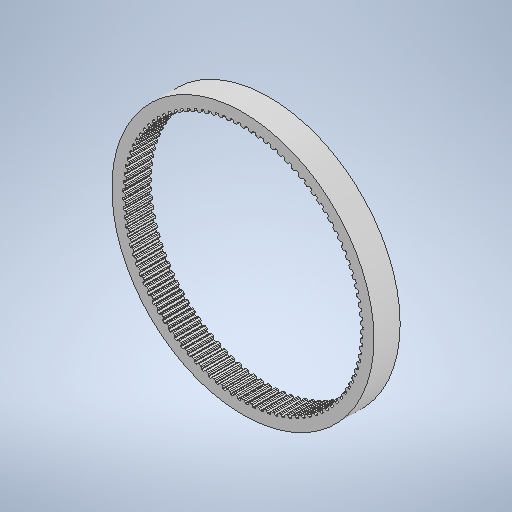
# Autodesk Inventor part: 3D_belt-MXL-100
Saved by Autodesk Inventor 2025.3 (Build 293356030, 356C)
## iProperties
Created: 2026-02-24
Part Number: 3D_belt-MXL-100
Material: 一般
Document SubType Name: Modeling
Designer: ibuki_ono
Density: 1 g/cm^3
Appearance: 既定
Author: ibuki_ono
## iProperties of the stored document 3D_belt-MXL-100_3D プリント.ipt
Created: 2026-02-24
Part Number: 3D_belt-MXL-100_3D プリント
Material: 一般
Document SubType Name: Modeling
Designer: ibuki_ono
Density: 1 g/cm^3
Appearance: 既定
Author: ibuki_ono
Autodesk Inventor part; units mm, degrees
(part 1 of 2)
ref_plane "YZ Plane" through (0, 0, 0) normal (1, 0, 0) x (0, 1, 0)
ref_plane "XZ Plane" through (0, 0, 0) normal (0, 1, 0) x (-1, 0, 0)
ref_plane "XY Plane" through (0, 0, 0) normal (0, 0, 1) x (1, 0, 0)
sketch "スケッチ1" plane through (0, 0, 0) normal (0, 0, 1) x (1, 0, 0)
  arc A0 (2.7701, 31.9665) -> (2.6427, 31.8908) centre (2.7591, 31.84) ccw
  line L0 (2.6427, 31.8908) -> (2.4611, 31.4752)
  arc A1 (2.2124, 31.3234) -> (2.4611, 31.4752) centre (2.2284, 31.5769) ccw
  line L1 (2.2124, 31.3234) -> (1.7309, 31.3537)
  arc A2 (1.5032, 31.5355) -> (1.7309, 31.3537) centre (1.7468, 31.6072) ccw
  line L2 (1.5032, 31.5355) -> (1.3751, 31.9706)
  arc A3 (1.3751, 31.9706) -> (1.2583, 32.0616) centre (1.2533, 31.9347) ccw
  arc A4 (1.2583, 32.0616) -> (0.7574, 32.0773) centre (0, 0) ccw
  arc A5 (0.7574, 32.0773) -> (0.6351, 31.9938) centre (0.7544, 31.9504) ccw
  line L3 (0.6351, 31.9938) -> (0.4799, 31.5676)
  arc A6 (0.2412, 31.4005) -> (0.4799, 31.5676) centre (0.2412, 31.6545) ccw
  line L4 (0.2412, 31.4005) -> (-0.2412, 31.4005)
  arc A7 (-0.4799, 31.5676) -> (-0.2412, 31.4005) centre (-0.2412, 31.6545) ccw
  line L5 (-0.4799, 31.5676) -> (-0.6351, 31.9938)
  arc A8 (-0.6351, 31.9938) -> (-0.7574, 32.0773) centre (-0.7544, 31.9504) ccw
  arc A9 (-0.7574, 32.0773) -> (-1.2583, 32.0616) centre (0, 0) ccw
  arc A10 (-1.2583, 32.0616) -> (-1.3751, 31.9706) centre (-1.2533, 31.9347) ccw
  line L6 (-1.3751, 31.9706) -> (-1.5032, 31.5355)
  arc A11 (-1.7309, 31.3537) -> (-1.5032, 31.5355) centre (-1.7468, 31.6072) ccw
  line L7 (-1.7309, 31.3537) -> (-2.2124, 31.3234)
  arc A12 (-2.4611, 31.4752) -> (-2.2124, 31.3234) centre (-2.2284, 31.5769) ccw
  line L8 (-2.4611, 31.4752) -> (-2.6427, 31.8908)
  arc A13 (-2.6427, 31.8908) -> (-2.7701, 31.9665) centre (-2.7591, 31.84) ccw
  arc A14 (-2.7701, 31.9665) -> (-3.2689, 31.9193) centre (0, 0) ccw
  arc A15 (-3.2689, 31.9193) -> (-3.3798, 31.8211) centre (-3.256, 31.793) ccw
  line L9 (-3.3798, 31.8211) -> (-3.4803, 31.3788)
  arc A16 (-3.6962, 31.1831) -> (-3.4803, 31.3788) centre (-3.728, 31.4351) ccw
  line L10 (-3.6962, 31.1831) -> (-4.1749, 31.1226)
  arc A17 (-4.4326, 31.2585) -> (-4.1749, 31.1226) centre (-4.2067, 31.3746) ccw
  line L11 (-4.4326, 31.2585) -> (-4.6399, 31.6619)
  arc A18 (-4.6399, 31.6619) -> (-4.7718, 31.7295) centre (-4.7529, 31.6039) ccw
  arc A19 (-4.7718, 31.7295) -> (-5.2667, 31.6511) centre (0, 0) ccw
  arc A20 (-5.2667, 31.6511) -> (-5.3712, 31.5461) centre (-5.2459, 31.5258) ccw
  line L12 (-5.3712, 31.5461) -> (-5.4438, 31.0984)
  arc A21 (-5.6469, 30.8895) -> (-5.4438, 31.0984) centre (-5.6945, 31.139) ccw
  line L13 (-5.6469, 30.8895) -> (-6.1208, 30.7991)
  arc A22 (-6.3866, 30.9185) -> (-6.1208, 30.7991) centre (-6.1684, 31.0486) ccw
  line L14 (-6.3866, 30.9185) -> (-6.6188, 31.3081)
  arc A23 (-6.6188, 31.3081) -> (-6.7547, 31.3672) centre (-6.7279, 31.2431) ccw
  arc A24 (-6.7547, 31.3672) -> (-7.2437, 31.2579) centre (0, 0) ccw
  arc A25 (-7.2437, 31.2579) -> (-7.3414, 31.1466) centre (-7.215, 31.1342) ccw
  line L15 (-7.3414, 31.1466) -> (-7.3857, 30.6952)
  arc A26 (-7.5753, 30.474) -> (-7.3857, 30.6952) centre (-7.6385, 30.72) ccw
  line L16 (-7.5753, 30.474) -> (-8.0427, 30.354)
  arc A27 (-8.3154, 30.4565) -> (-8.0427, 30.354) centre (-8.1058, 30.6) ccw
  line L17 (-8.3154, 30.4565) -> (-8.5716, 30.8307)
  arc A28 (-8.5716, 30.8307) -> (-8.7109, 30.8812) centre (-8.6764, 30.759) ccw
  arc A29 (-8.7109, 30.8812) -> (-9.1921, 30.7414) centre (0, 0) ccw
  arc A30 (-9.1921, 30.7414) -> (-9.2827, 30.6242) centre (-9.1557, 30.6197) ccw
  line L18 (-9.2827, 30.6242) -> (-9.2985, 30.1709)
  arc A31 (-9.4738, 29.9382) -> (-9.2985, 30.1709) centre (-9.5523, 30.1798) ccw
  line L19 (-9.4738, 29.9382) -> (-9.9327, 29.7891)
  arc A32 (-10.2114, 29.8743) -> (-9.9327, 29.7891) centre (-10.0112, 30.0307) ccw
  line L20 (-10.2114, 29.8743) -> (-10.4906, 30.2317)
  arc A33 (-10.4906, 30.2317) -> (-10.6328, 30.2733) centre (-10.5907, 30.1535) ccw
  arc A34 (-10.6328, 30.2733) -> (-11.1043, 30.1036) centre (0, 0) ccw
  arc A35 (-11.1043, 30.1036) -> (-11.1872, 29.9809) centre (-11.0603, 29.9844) ccw
  line L21 (-11.1872, 29.9809) -> (-11.1746, 29.5275)
  arc A36 (-11.335, 29.2842) -> (-11.1746, 29.5275) centre (-11.4285, 29.5204) ccw
  line L22 (-11.335, 29.2842) -> (-11.7836, 29.1066)
  arc A37 (-12.067, 29.1741) -> (-11.7836, 29.1066) centre (-11.8771, 29.3428) ccw
  line L23 (-12.067, 29.1741) -> (-12.3682, 29.5133)
  arc A38 (-12.3682, 29.5133) -> (-12.5127, 29.5459) centre (-12.4631, 29.429) ccw
  arc A39 (-12.5127, 29.5459) -> (-12.9726, 29.3469) centre (0, 0) ccw
  arc A40 (-12.9726, 29.3469) -> (-13.0477, 29.2193) centre (-12.9212, 29.2308) ccw
  line L24 (-13.0477, 29.2193) -> (-13.0066, 28.7676)
  arc A41 (-13.1514, 28.5147) -> (-13.0066, 28.7676) centre (-13.2595, 28.7446) ccw
  line L25 (-13.1514, 28.5147) -> (-13.588, 28.3093)
  arc A42 (-13.8751, 28.3589) -> (-13.588, 28.3093) centre (-13.6961, 28.5391) ccw
  line L26 (-13.8751, 28.3589) -> (-14.1969, 28.6785)
  arc A43 (-14.1969, 28.6785) -> (-14.3432, 28.702) centre (-14.2864, 28.5884) ccw
  arc A44 (-14.3432, 28.702) -> (-14.7897, 28.4745) centre (0, 0) ccw
  arc A45 (-14.7897, 28.4745) -> (-14.8566, 28.3423) centre (-14.7311, 28.3618) ccw
  line L27 (-14.8566, 28.3423) -> (-14.7872, 27.8941)
  arc A46 (-14.9159, 27.6327) -> (-14.7872, 27.8941) centre (-15.0383, 27.8553) ccw
  line L28 (-14.9159, 27.6327) -> (-15.3387, 27.4002)
  arc A47 (-15.6284, 27.4317) -> (-15.3387, 27.4002) centre (-15.4611, 27.6228) ccw
  line L29 (-15.6284, 27.4317) -> (-15.9696, 27.7305)
  arc A48 (-15.9696, 27.7305) -> (-16.1171, 27.7447) centre (-16.0533, 27.6349) ccw
  arc A49 (-16.1171, 27.7447) -> (-16.5484, 27.4896) centre (0, 0) ccw
  arc A50 (-16.5484, 27.4896) -> (-16.6069, 27.3536) centre (-16.4829, 27.3808) ccw
  line L30 (-16.6069, 27.3536) -> (-16.5096, 26.9106)
  arc A51 (-16.6215, 26.6416) -> (-16.5096, 26.9106) centre (-16.7576, 26.856) ccw
  line L31 (-16.6215, 26.6416) -> (-17.0289, 26.383)
  arc A52 (-17.32, 26.3963) -> (-17.0289, 26.383) centre (-17.165, 26.5975) ccw
  line L32 (-17.32, 26.3963) -> (-17.6793, 26.673)
  arc A53 (-17.6793, 26.673) -> (-17.8274, 26.678) centre (-17.7568, 26.5724) ccw
  arc A54 (-17.8274, 26.678) -> (-18.2418, 26.3963) centre (0, 0) ccw
  arc A55 (-18.2418, 26.3963) -> (-18.2917, 26.2568) centre (-18.1696, 26.2918) ccw
  line L33 (-18.2917, 26.2568) -> (-18.1667, 25.8208)
  arc A56 (-18.2616, 25.5453) -> (-18.1667, 25.8208) centre (-18.4109, 25.7508) ccw
  line L34 (-18.2616, 25.5453) -> (-18.6519, 25.2617)
  arc A57 (-18.9432, 25.2566) -> (-18.6519, 25.2617) centre (-18.8012, 25.4672) ccw
  line L35 (-18.9432, 25.2566) -> (-19.3193, 25.5103)
  arc A58 (-19.3193, 25.5103) -> (-19.4673, 25.5059) centre (-19.3903, 25.405) ccw
  arc A59 (-19.4673, 25.5059) -> (-19.8633, 25.1988) centre (0, 0) ccw
  arc A60 (-19.8633, 25.1988) -> (-19.9043, 25.0565) centre (-19.7847, 25.0991) ccw
  line L36 (-19.9043, 25.0565) -> (-19.7522, 24.6292)
  arc A61 (-19.8295, 24.3483) -> (-19.7522, 24.6292) centre (-19.9914, 24.544) ccw
  line L37 (-19.8295, 24.3483) -> (-20.2013, 24.0407)
  arc A62 (-20.4917, 24.0173) -> (-20.2013, 24.0407) centre (-20.3632, 24.2364) ccw
  line L38 (-20.4917, 24.0173) -> (-20.8829, 24.2469)
  arc A63 (-20.8829, 24.2469) -> (-21.0305, 24.2332) centre (-20.9472, 24.1373) ccw
  arc A64 (-21.0305, 24.2332) -> (-21.4063, 23.9018) centre (0, 0) ccw
  arc A65 (-21.4063, 23.9018) -> (-21.4383, 23.7572) centre (-21.3216, 23.8072) ccw
  line L39 (-21.4383, 23.7572) -> (-21.2597, 23.3403)
  arc A66 (-21.3192, 23.0551) -> (-21.2597, 23.3403) centre (-21.4931, 23.2403) ccw
  line L40 (-21.3192, 23.0551) -> (-21.671, 22.7248)
  arc A67 (-21.9594, 22.6833) -> (-21.671, 22.7248) centre (-21.8448, 22.91) ccw
  line L41 (-21.9594, 22.6833) -> (-22.3642, 22.8878)
  arc A68 (-22.3642, 22.8878) -> (-22.5106, 22.8649) centre (-22.4215, 22.7744) ccw
  arc A69 (-22.5106, 22.8649) -> (-22.8649, 22.5106) centre (0, 0) ccw
  arc A70 (-22.8649, 22.5106) -> (-22.8878, 22.3642) centre (-22.7744, 22.4215) ccw
  line L42 (-22.8878, 22.3642) -> (-22.6833, 21.9594)
  arc A71 (-22.7248, 21.671) -> (-22.6833, 21.9594) centre (-22.91, 21.8448) ccw
  line L43 (-22.7248, 21.671) -> (-23.0551, 21.3192)
  arc A72 (-23.3403, 21.2597) -> (-23.0551, 21.3192) centre (-23.2403, 21.4931) ccw
  line L44 (-23.3403, 21.2597) -> (-23.7572, 21.4383)
  arc A73 (-23.7572, 21.4383) -> (-23.9018, 21.4063) centre (-23.8072, 21.3216) ccw
  arc A74 (-23.9018, 21.4063) -> (-24.2332, 21.0305) centre (0, 0) ccw
  arc A75 (-24.2332, 21.0305) -> (-24.2469, 20.8829) centre (-24.1373, 20.9472) ccw
  line L45 (-24.2469, 20.8829) -> (-24.0173, 20.4917)
  arc A76 (-24.0407, 20.2013) -> (-24.0173, 20.4917) centre (-24.2364, 20.3632) ccw
  line L46 (-24.0407, 20.2013) -> (-24.3483, 19.8295)
  arc A77 (-24.6292, 19.7522) -> (-24.3483, 19.8295) centre (-24.544, 19.9914) ccw
  line L47 (-24.6292, 19.7522) -> (-25.0565, 19.9043)
  arc A78 (-25.0565, 19.9043) -> (-25.1988, 19.8633) centre (-25.0991, 19.7847) ccw
  arc A79 (-25.1988, 19.8633) -> (-25.5059, 19.4673) centre (0, 0) ccw
  arc A80 (-25.5059, 19.4673) -> (-25.5103, 19.3193) centre (-25.405, 19.3903) ccw
  line L48 (-25.5103, 19.3193) -> (-25.2566, 18.9432)
  arc A81 (-25.2617, 18.6519) -> (-25.2566, 18.9432) centre (-25.4672, 18.8012) ccw
  line L49 (-25.2617, 18.6519) -> (-25.5453, 18.2616)
  arc A82 (-25.8208, 18.1667) -> (-25.5453, 18.2616) centre (-25.7508, 18.4109) ccw
  line L50 (-25.8208, 18.1667) -> (-26.2568, 18.2917)
  arc A83 (-26.2568, 18.2917) -> (-26.3963, 18.2418) centre (-26.2918, 18.1696) ccw
  arc A84 (-26.3963, 18.2418) -> (-26.678, 17.8274) centre (0, 0) ccw
  arc A85 (-26.678, 17.8274) -> (-26.673, 17.6793) centre (-26.5724, 17.7568) ccw
  line L51 (-26.673, 17.6793) -> (-26.3963, 17.32)
  arc A86 (-26.383, 17.0289) -> (-26.3963, 17.32) centre (-26.5975, 17.165) ccw
  line L52 (-26.383, 17.0289) -> (-26.6416, 16.6215)
  arc A87 (-26.9106, 16.5096) -> (-26.6416, 16.6215) centre (-26.856, 16.7576) ccw
  line L53 (-26.9106, 16.5096) -> (-27.3536, 16.6069)
  arc A88 (-27.3536, 16.6069) -> (-27.4896, 16.5484) centre (-27.3808, 16.4829) ccw
  arc A89 (-27.4896, 16.5484) -> (-27.7447, 16.1171) centre (0, 0) ccw
  arc A90 (-27.7447, 16.1171) -> (-27.7305, 15.9696) centre (-27.6349, 16.0533) ccw
  line L54 (-27.7305, 15.9696) -> (-27.4317, 15.6284)
  arc A91 (-27.4002, 15.3387) -> (-27.4317, 15.6284) centre (-27.6228, 15.4611) ccw
  line L55 (-27.4002, 15.3387) -> (-27.6327, 14.9159)
  arc A92 (-27.8941, 14.7872) -> (-27.6327, 14.9159) centre (-27.8553, 15.0383) ccw
  line L56 (-27.8941, 14.7872) -> (-28.3423, 14.8566)
  arc A93 (-28.3423, 14.8566) -> (-28.4745, 14.7897) centre (-28.3618, 14.7311) ccw
  arc A94 (-28.4745, 14.7897) -> (-28.702, 14.3432) centre (0, 0) ccw
  arc A95 (-28.702, 14.3432) -> (-28.6785, 14.1969) centre (-28.5884, 14.2864) ccw
  line L57 (-28.6785, 14.1969) -> (-28.3589, 13.8751)
  arc A96 (-28.3093, 13.588) -> (-28.3589, 13.8751) centre (-28.5391, 13.6961) ccw
  line L58 (-28.3093, 13.588) -> (-28.5147, 13.1514)
  arc A97 (-28.7676, 13.0066) -> (-28.5147, 13.1514) centre (-28.7446, 13.2595) ccw
  line L59 (-28.7676, 13.0066) -> (-29.2193, 13.0477)
  arc A98 (-29.2193, 13.0477) -> (-29.3469, 12.9726) centre (-29.2308, 12.9212) ccw
  arc A99 (-29.3469, 12.9726) -> (-29.5459, 12.5127) centre (0, 0) ccw
  arc A100 (-29.5459, 12.5127) -> (-29.5133, 12.3682) centre (-29.429, 12.4631) ccw
  line L60 (-29.5133, 12.3682) -> (-29.1741, 12.067)
  arc A101 (-29.1066, 11.7836) -> (-29.1741, 12.067) centre (-29.3428, 11.8771) ccw
  line L61 (-29.1066, 11.7836) -> (-29.2842, 11.335)
  arc A102 (-29.5275, 11.1746) -> (-29.2842, 11.335) centre (-29.5204, 11.4285) ccw
  line L62 (-29.5275, 11.1746) -> (-29.9809, 11.1872)
  arc A103 (-29.9809, 11.1872) -> (-30.1036, 11.1043) centre (-29.9844, 11.0603) ccw
  arc A104 (-30.1036, 11.1043) -> (-30.2733, 10.6328) centre (0, 0) ccw
  arc A105 (-30.2733, 10.6328) -> (-30.2317, 10.4906) centre (-30.1535, 10.5907) ccw
  line L63 (-30.2317, 10.4906) -> (-29.8743, 10.2114)
  arc A106 (-29.7891, 9.9327) -> (-29.8743, 10.2114) centre (-30.0307, 10.0112) ccw
  line L64 (-29.7891, 9.9327) -> (-29.9382, 9.4738)
  arc A107 (-30.1709, 9.2985) -> (-29.9382, 9.4738) centre (-30.1798, 9.5523) ccw
  line L65 (-30.1709, 9.2985) -> (-30.6242, 9.2827)
  arc A108 (-30.6242, 9.2827) -> (-30.7414, 9.1921) centre (-30.6197, 9.1557) ccw
  arc A109 (-30.7414, 9.1921) -> (-30.8812, 8.7109) centre (0, 0) ccw
  arc A110 (-30.8812, 8.7109) -> (-30.8307, 8.5716) centre (-30.759, 8.6764) ccw
  line L66 (-30.8307, 8.5716) -> (-30.4565, 8.3154)
  arc A111 (-30.354, 8.0427) -> (-30.4565, 8.3154) centre (-30.6, 8.1058) ccw
  line L67 (-30.354, 8.0427) -> (-30.474, 7.5753)
  arc A112 (-30.6952, 7.3857) -> (-30.474, 7.5753) centre (-30.72, 7.6385) ccw
  line L68 (-30.6952, 7.3857) -> (-31.1466, 7.3414)
  arc A113 (-31.1466, 7.3414) -> (-31.2579, 7.2437) centre (-31.1342, 7.215) ccw
  arc A114 (-31.2579, 7.2437) -> (-31.3672, 6.7547) centre (0, 0) ccw
  arc A115 (-31.3672, 6.7547) -> (-31.3081, 6.6188) centre (-31.2431, 6.7279) ccw
  line L69 (-31.3081, 6.6188) -> (-30.9185, 6.3866)
  arc A116 (-30.7991, 6.1208) -> (-30.9185, 6.3866) centre (-31.0486, 6.1684) ccw
  line L70 (-30.7991, 6.1208) -> (-30.8895, 5.6469)
  arc A117 (-31.0984, 5.4438) -> (-30.8895, 5.6469) centre (-31.139, 5.6945) ccw
  line L71 (-31.0984, 5.4438) -> (-31.5461, 5.3712)
  arc A118 (-31.5461, 5.3712) -> (-31.6511, 5.2667) centre (-31.5258, 5.2459) ccw
  arc A119 (-31.6511, 5.2667) -> (-31.7295, 4.7718) centre (0, 0) ccw
  arc A120 (-31.7295, 4.7718) -> (-31.6619, 4.6399) centre (-31.6039, 4.7529) ccw
  line L72 (-31.6619, 4.6399) -> (-31.2585, 4.4326)
  arc A121 (-31.1226, 4.1749) -> (-31.2585, 4.4326) centre (-31.3746, 4.2067) ccw
  line L73 (-31.1226, 4.1749) -> (-31.1831, 3.6962)
  arc A122 (-31.3788, 3.4803) -> (-31.1831, 3.6962) centre (-31.4351, 3.728) ccw
  line L74 (-31.3788, 3.4803) -> (-31.8211, 3.3798)
  arc A123 (-31.8211, 3.3798) -> (-31.9193, 3.2689) centre (-31.793, 3.256) ccw
  arc A124 (-31.9193, 3.2689) -> (-31.9665, 2.7701) centre (0, 0) ccw
  arc A125 (-31.9665, 2.7701) -> (-31.8908, 2.6427) centre (-31.84, 2.7591) ccw
  line L75 (-31.8908, 2.6427) -> (-31.4752, 2.4611)
  arc A126 (-31.3234, 2.2124) -> (-31.4752, 2.4611) centre (-31.5769, 2.2284) ccw
  line L76 (-31.3234, 2.2124) -> (-31.3537, 1.7309)
  arc A127 (-31.5355, 1.5032) -> (-31.3537, 1.7309) centre (-31.6072, 1.7468) ccw
  line L77 (-31.5355, 1.5032) -> (-31.9706, 1.3751)
  arc A128 (-31.9706, 1.3751) -> (-32.0616, 1.2583) centre (-31.9347, 1.2533) ccw
  arc A129 (-32.0616, 1.2583) -> (-32.0773, 0.7574) centre (0, 0) ccw
  arc A130 (-32.0773, 0.7574) -> (-31.9938, 0.6351) centre (-31.9504, 0.7544) ccw
  line L78 (-31.9938, 0.6351) -> (-31.5676, 0.4799)
  arc A131 (-31.4005, 0.2412) -> (-31.5676, 0.4799) centre (-31.6545, 0.2412) ccw
  line L79 (-31.4005, 0.2412) -> (-31.4005, -0.2412)
  arc A132 (-31.5676, -0.4799) -> (-31.4005, -0.2412) centre (-31.6545, -0.2412) ccw
  line L80 (-31.5676, -0.4799) -> (-31.9938, -0.6351)
  arc A133 (-31.9938, -0.6351) -> (-32.0773, -0.7574) centre (-31.9504, -0.7544) ccw
  arc A134 (-32.0773, -0.7574) -> (-32.0616, -1.2583) centre (0, 0) ccw
  arc A135 (-32.0616, -1.2583) -> (-31.9706, -1.3751) centre (-31.9347, -1.2533) ccw
  line L81 (-31.9706, -1.3751) -> (-31.5355, -1.5032)
  arc A136 (-31.3537, -1.7309) -> (-31.5355, -1.5032) centre (-31.6072, -1.7468) ccw
  line L82 (-31.3537, -1.7309) -> (-31.3234, -2.2124)
  arc A137 (-31.4752, -2.4611) -> (-31.3234, -2.2124) centre (-31.5769, -2.2284) ccw
  line L83 (-31.4752, -2.4611) -> (-31.8908, -2.6427)
  arc A138 (-31.8908, -2.6427) -> (-31.9665, -2.7701) centre (-31.84, -2.7591) ccw
  arc A139 (-31.9665, -2.7701) -> (-31.9193, -3.2689) centre (0, 0) ccw
  arc A140 (-31.9193, -3.2689) -> (-31.8211, -3.3798) centre (-31.793, -3.256) ccw
  line L84 (-31.8211, -3.3798) -> (-31.3788, -3.4803)
  arc A141 (-31.1831, -3.6962) -> (-31.3788, -3.4803) centre (-31.4351, -3.728) ccw
  line L85 (-31.1831, -3.6962) -> (-31.1226, -4.1749)
  arc A142 (-31.2585, -4.4326) -> (-31.1226, -4.1749) centre (-31.3746, -4.2067) ccw
  line L86 (-31.2585, -4.4326) -> (-31.6619, -4.6399)
  arc A143 (-31.6619, -4.6399) -> (-31.7295, -4.7718) centre (-31.6039, -4.7529) ccw
  arc A144 (-31.7295, -4.7718) -> (-31.6511, -5.2667) centre (0, 0) ccw
  arc A145 (-31.6511, -5.2667) -> (-31.5461, -5.3712) centre (-31.5258, -5.2459) ccw
  line L87 (-31.5461, -5.3712) -> (-31.0984, -5.4438)
  arc A146 (-30.8895, -5.6469) -> (-31.0984, -5.4438) centre (-31.139, -5.6945) ccw
  line L88 (-30.8895, -5.6469) -> (-30.7991, -6.1208)
  arc A147 (-30.9185, -6.3866) -> (-30.7991, -6.1208) centre (-31.0486, -6.1684) ccw
  line L89 (-30.9185, -6.3866) -> (-31.3081, -6.6188)
  arc A148 (-31.3081, -6.6188) -> (-31.3672, -6.7547) centre (-31.2431, -6.7279) ccw
  arc A149 (-31.3672, -6.7547) -> (-31.2579, -7.2437) centre (0, 0) ccw
  arc A150 (-31.2579, -7.2437) -> (-31.1466, -7.3414) centre (-31.1342, -7.215) ccw
  line L90 (-31.1466, -7.3414) -> (-30.6952, -7.3857)
  arc A151 (-30.474, -7.5753) -> (-30.6952, -7.3857) centre (-30.72, -7.6385) ccw
  line L91 (-30.474, -7.5753) -> (-30.354, -8.0427)
  arc A152 (-30.4565, -8.3154) -> (-30.354, -8.0427) centre (-30.6, -8.1058) ccw
  line L92 (-30.4565, -8.3154) -> (-30.8307, -8.5716)
  arc A153 (-30.8307, -8.5716) -> (-30.8812, -8.7109) centre (-30.759, -8.6764) ccw
  arc A154 (-30.8812, -8.7109) -> (-30.7414, -9.1921) centre (0, 0) ccw
  arc A155 (-30.7414, -9.1921) -> (-30.6242, -9.2827) centre (-30.6197, -9.1557) ccw
  line L93 (-30.6242, -9.2827) -> (-30.1709, -9.2985)
  arc A156 (-29.9382, -9.4738) -> (-30.1709, -9.2985) centre (-30.1798, -9.5523) ccw
  line L94 (-29.9382, -9.4738) -> (-29.7891, -9.9327)
  arc A157 (-29.8743, -10.2114) -> (-29.7891, -9.9327) centre (-30.0307, -10.0112) ccw
  line L95 (-29.8743, -10.2114) -> (-30.2317, -10.4906)
  arc A158 (-30.2317, -10.4906) -> (-30.2733, -10.6328) centre (-30.1535, -10.5907) ccw
  arc A159 (-30.2733, -10.6328) -> (-30.1036, -11.1043) centre (0, 0) ccw
  arc A160 (-30.1036, -11.1043) -> (-29.9809, -11.1872) centre (-29.9844, -11.0603) ccw
  line L96 (-29.9809, -11.1872) -> (-29.5275, -11.1746)
  arc A161 (-29.2842, -11.335) -> (-29.5275, -11.1746) centre (-29.5204, -11.4285) ccw
  line L97 (-29.2842, -11.335) -> (-29.1066, -11.7836)
  arc A162 (-29.1741, -12.067) -> (-29.1066, -11.7836) centre (-29.3428, -11.8771) ccw
  line L98 (-29.1741, -12.067) -> (-29.5133, -12.3682)
  arc A163 (-29.5133, -12.3682) -> (-29.5459, -12.5127) centre (-29.429, -12.4631) ccw
  arc A164 (-29.5459, -12.5127) -> (-29.3469, -12.9726) centre (0, 0) ccw
  arc A165 (-29.3469, -12.9726) -> (-29.2193, -13.0477) centre (-29.2308, -12.9212) ccw
  line L99 (-29.2193, -13.0477) -> (-28.7676, -13.0066)
  arc A166 (-28.5147, -13.1514) -> (-28.7676, -13.0066) centre (-28.7446, -13.2595) ccw
  line L100 (-28.5147, -13.1514) -> (-28.3093, -13.588)
  arc A167 (-28.3589, -13.8751) -> (-28.3093, -13.588) centre (-28.5391, -13.6961) ccw
  line L101 (-28.3589, -13.8751) -> (-28.6785, -14.1969)
  arc A168 (-28.6785, -14.1969) -> (-28.702, -14.3432) centre (-28.5884, -14.2864) ccw
  arc A169 (-28.702, -14.3432) -> (-28.4745, -14.7897) centre (0, 0) ccw
  arc A170 (-28.4745, -14.7897) -> (-28.3423, -14.8566) centre (-28.3618, -14.7311) ccw
  line L102 (-28.3423, -14.8566) -> (-27.8941, -14.7872)
  arc A171 (-27.6327, -14.9159) -> (-27.8941, -14.7872) centre (-27.8553, -15.0383) ccw
  line L103 (-27.6327, -14.9159) -> (-27.4002, -15.3387)
  arc A172 (-27.4317, -15.6284) -> (-27.4002, -15.3387) centre (-27.6228, -15.4611) ccw
  line L104 (-27.4317, -15.6284) -> (-27.7305, -15.9696)
  arc A173 (-27.7305, -15.9696) -> (-27.7447, -16.1171) centre (-27.6349, -16.0533) ccw
  arc A174 (-27.7447, -16.1171) -> (-27.4896, -16.5484) centre (0, 0) ccw
  arc A175 (-27.4896, -16.5484) -> (-27.3536, -16.6069) centre (-27.3808, -16.4829) ccw
  line L105 (-27.3536, -16.6069) -> (-26.9106, -16.5096)
  arc A176 (-26.6416, -16.6215) -> (-26.9106, -16.5096) centre (-26.856, -16.7576) ccw
  line L106 (-26.6416, -16.6215) -> (-26.383, -17.0289)
  arc A177 (-26.3963, -17.32) -> (-26.383, -17.0289) centre (-26.5975, -17.165) ccw
  line L107 (-26.3963, -17.32) -> (-26.673, -17.6793)
  arc A178 (-26.673, -17.6793) -> (-26.678, -17.8274) centre (-26.5724, -17.7568) ccw
  arc A179 (-26.678, -17.8274) -> (-26.3963, -18.2418) centre (0, 0) ccw
  arc A180 (-26.3963, -18.2418) -> (-26.2568, -18.2917) centre (-26.2918, -18.1696) ccw
  line L108 (-26.2568, -18.2917) -> (-25.8208, -18.1667)
  arc A181 (-25.5453, -18.2616) -> (-25.8208, -18.1667) centre (-25.7508, -18.4109) ccw
  line L109 (-25.5453, -18.2616) -> (-25.2617, -18.6519)
  arc A182 (-25.2566, -18.9432) -> (-25.2617, -18.6519) centre (-25.4672, -18.8012) ccw
  line L110 (-25.2566, -18.9432) -> (-25.5103, -19.3193)
  arc A183 (-25.5103, -19.3193) -> (-25.5059, -19.4673) centre (-25.405, -19.3903) ccw
  arc A184 (-25.5059, -19.4673) -> (-25.1988, -19.8633) centre (0, 0) ccw
  arc A185 (-25.1988, -19.8633) -> (-25.0565, -19.9043) centre (-25.0991, -19.7847) ccw
  line L111 (-25.0565, -19.9043) -> (-24.6292, -19.7522)
  arc A186 (-24.3483, -19.8295) -> (-24.6292, -19.7522) centre (-24.544, -19.9914) ccw
  line L112 (-24.3483, -19.8295) -> (-24.0407, -20.2013)
  arc A187 (-24.0173, -20.4917) -> (-24.0407, -20.2013) centre (-24.2364, -20.3632) ccw
  line L113 (-24.0173, -20.4917) -> (-24.2469, -20.8829)
  arc A188 (-24.2469, -20.8829) -> (-24.2332, -21.0305) centre (-24.1373, -20.9472) ccw
  arc A189 (-24.2332, -21.0305) -> (-23.9018, -21.4063) centre (0, 0) ccw
  arc A190 (-23.9018, -21.4063) -> (-23.7572, -21.4383) centre (-23.8072, -21.3216) ccw
  line L114 (-23.7572, -21.4383) -> (-23.3403, -21.2597)
  arc A191 (-23.0551, -21.3192) -> (-23.3403, -21.2597) centre (-23.2403, -21.4931) ccw
  line L115 (-23.0551, -21.3192) -> (-22.7248, -21.671)
  arc A192 (-22.6833, -21.9594) -> (-22.7248, -21.671) centre (-22.91, -21.8448) ccw
  line L116 (-22.6833, -21.9594) -> (-22.8878, -22.3642)
  arc A193 (-22.8878, -22.3642) -> (-22.8649, -22.5106) centre (-22.7744, -22.4215) ccw
  arc A194 (-22.8649, -22.5106) -> (-22.5106, -22.8649) centre (0, 0) ccw
  arc A195 (-22.5106, -22.8649) -> (-22.3642, -22.8878) centre (-22.4215, -22.7744) ccw
  line L117 (-22.3642, -22.8878) -> (-21.9594, -22.6833)
  arc A196 (-21.671, -22.7248) -> (-21.9594, -22.6833) centre (-21.8448, -22.91) ccw
  line L118 (-21.671, -22.7248) -> (-21.3192, -23.0551)
  arc A197 (-21.2597, -23.3403) -> (-21.3192, -23.0551) centre (-21.4931, -23.2403) ccw
  line L119 (-21.2597, -23.3403) -> (-21.4383, -23.7572)
  arc A198 (-21.4383, -23.7572) -> (-21.4063, -23.9018) centre (-21.3216, -23.8072) ccw
  arc A199 (-21.4063, -23.9018) -> (-21.0305, -24.2332) centre (0, 0) ccw
  arc A200 (-21.0305, -24.2332) -> (-20.8829, -24.2469) centre (-20.9472, -24.1373) ccw
  line L120 (-20.8829, -24.2469) -> (-20.4917, -24.0173)
  arc A201 (-20.2013, -24.0407) -> (-20.4917, -24.0173) centre (-20.3632, -24.2364) ccw
  line L121 (-20.2013, -24.0407) -> (-19.8295, -24.3483)
  arc A202 (-19.7522, -24.6292) -> (-19.8295, -24.3483) centre (-19.9914, -24.544) ccw
  line L122 (-19.7522, -24.6292) -> (-19.9043, -25.0565)
  arc A203 (-19.9043, -25.0565) -> (-19.8633, -25.1988) centre (-19.7847, -25.0991) ccw
  arc A204 (-19.8633, -25.1988) -> (-19.4673, -25.5059) centre (0, 0) ccw
  arc A205 (-19.4673, -25.5059) -> (-19.3193, -25.5103) centre (-19.3903, -25.405) ccw
  line L123 (-19.3193, -25.5103) -> (-18.9432, -25.2566)
  arc A206 (-18.6519, -25.2617) -> (-18.9432, -25.2566) centre (-18.8012, -25.4672) ccw
  line L124 (-18.6519, -25.2617) -> (-18.2616, -25.5453)
  arc A207 (-18.1667, -25.8208) -> (-18.2616, -25.5453) centre (-18.4109, -25.7508) ccw
  line L125 (-18.1667, -25.8208) -> (-18.2917, -26.2568)
  arc A208 (-18.2917, -26.2568) -> (-18.2418, -26.3963) centre (-18.1696, -26.2918) ccw
  arc A209 (-18.2418, -26.3963) -> (-17.8274, -26.678) centre (0, 0) ccw
  arc A210 (-17.8274, -26.678) -> (-17.6793, -26.673) centre (-17.7568, -26.5724) ccw
  line L126 (-17.6793, -26.673) -> (-17.32, -26.3963)
  arc A211 (-17.0289, -26.383) -> (-17.32, -26.3963) centre (-17.165, -26.5975) ccw
  line L127 (-17.0289, -26.383) -> (-16.6215, -26.6416)
  arc A212 (-16.5096, -26.9106) -> (-16.6215, -26.6416) centre (-16.7576, -26.856) ccw
  line L128 (-16.5096, -26.9106) -> (-16.6069, -27.3536)
  arc A213 (-16.6069, -27.3536) -> (-16.5484, -27.4896) centre (-16.4829, -27.3808) ccw
  arc A214 (-16.5484, -27.4896) -> (-16.1171, -27.7447) centre (0, 0) ccw
  arc A215 (-16.1171, -27.7447) -> (-15.9696, -27.7305) centre (-16.0533, -27.6349) ccw
  line L129 (-15.9696, -27.7305) -> (-15.6284, -27.4317)
  arc A216 (-15.3387, -27.4002) -> (-15.6284, -27.4317) centre (-15.4611, -27.6228) ccw
  line L130 (-15.3387, -27.4002) -> (-14.9159, -27.6327)
  arc A217 (-14.7872, -27.8941) -> (-14.9159, -27.6327) centre (-15.0383, -27.8553) ccw
  line L131 (-14.7872, -27.8941) -> (-14.8566, -28.3423)
  arc A218 (-14.8566, -28.3423) -> (-14.7897, -28.4745) centre (-14.7311, -28.3618) ccw
  arc A219 (-14.7897, -28.4745) -> (-14.3432, -28.702) centre (0, 0) ccw
  arc A220 (-14.3432, -28.702) -> (-14.1969, -28.6785) centre (-14.2864, -28.5884) ccw
  line L132 (-14.1969, -28.6785) -> (-13.8751, -28.3589)
  arc A221 (-13.588, -28.3093) -> (-13.8751, -28.3589) centre (-13.6961, -28.5391) ccw
  line L133 (-13.588, -28.3093) -> (-13.1514, -28.5147)
  arc A222 (-13.0066, -28.7676) -> (-13.1514, -28.5147) centre (-13.2595, -28.7446) ccw
  line L134 (-13.0066, -28.7676) -> (-13.0477, -29.2193)
  arc A223 (-13.0477, -29.2193) -> (-12.9726, -29.3469) centre (-12.9212, -29.2308) ccw
  arc A224 (-12.9726, -29.3469) -> (-12.5127, -29.5459) centre (0, 0) ccw
  arc A225 (-12.5127, -29.5459) -> (-12.3682, -29.5133) centre (-12.4631, -29.429) ccw
  line L135 (-12.3682, -29.5133) -> (-12.067, -29.1741)
  arc A226 (-11.7836, -29.1066) -> (-12.067, -29.1741) centre (-11.8771, -29.3428) ccw
  line L136 (-11.7836, -29.1066) -> (-11.335, -29.2842)
  arc A227 (-11.1746, -29.5275) -> (-11.335, -29.2842) centre (-11.4285, -29.5204) ccw
  line L137 (-11.1746, -29.5275) -> (-11.1872, -29.9809)
  arc A228 (-11.1872, -29.9809) -> (-11.1043, -30.1036) centre (-11.0603, -29.9844) ccw
  arc A229 (-11.1043, -30.1036) -> (-10.6328, -30.2733) centre (0, 0) ccw
  arc A230 (-10.6328, -30.2733) -> (-10.4906, -30.2317) centre (-10.5907, -30.1535) ccw
  line L138 (-10.4906, -30.2317) -> (-10.2114, -29.8743)
  arc A231 (-9.9327, -29.7891) -> (-10.2114, -29.8743) centre (-10.0112, -30.0307) ccw
  line L139 (-9.9327, -29.7891) -> (-9.4738, -29.9382)
  arc A232 (-9.2985, -30.1709) -> (-9.4738, -29.9382) centre (-9.5523, -30.1798) ccw
  line L140 (-9.2985, -30.1709) -> (-9.2827, -30.6242)
  arc A233 (-9.2827, -30.6242) -> (-9.1921, -30.7414) centre (-9.1557, -30.6197) ccw
  arc A234 (-9.1921, -30.7414) -> (-8.7109, -30.8812) centre (0, 0) ccw
  arc A235 (-8.7109, -30.8812) -> (-8.5716, -30.8307) centre (-8.6764, -30.759) ccw
  line L141 (-8.5716, -30.8307) -> (-8.3154, -30.4565)
  arc A236 (-8.0427, -30.354) -> (-8.3154, -30.4565) centre (-8.1058, -30.6) ccw
  line L142 (-8.0427, -30.354) -> (-7.5753, -30.474)
  arc A237 (-7.3857, -30.6952) -> (-7.5753, -30.474) centre (-7.6385, -30.72) ccw
  line L143 (-7.3857, -30.6952) -> (-7.3414, -31.1466)
  arc A238 (-7.3414, -31.1466) -> (-7.2437, -31.2579) centre (-7.215, -31.1342) ccw
  arc A239 (-7.2437, -31.2579) -> (-6.7547, -31.3672) centre (0, 0) ccw
  arc A240 (-6.7547, -31.3672) -> (-6.6188, -31.3081) centre (-6.7279, -31.2431) ccw
  line L144 (-6.6188, -31.3081) -> (-6.3866, -30.9185)
  arc A241 (-6.1208, -30.7991) -> (-6.3866, -30.9185) centre (-6.1684, -31.0486) ccw
  line L145 (-6.1208, -30.7991) -> (-5.6469, -30.8895)
  arc A242 (-5.4438, -31.0984) -> (-5.6469, -30.8895) centre (-5.6945, -31.139) ccw
  line L146 (-5.4438, -31.0984) -> (-5.3712, -31.5461)
  arc A243 (-5.3712, -31.5461) -> (-5.2667, -31.6511) centre (-5.2459, -31.5258) ccw
  arc A244 (-5.2667, -31.6511) -> (-4.7718, -31.7295) centre (0, 0) ccw
  arc A245 (-4.7718, -31.7295) -> (-4.6399, -31.6619) centre (-4.7529, -31.6039) ccw
  line L147 (-4.6399, -31.6619) -> (-4.4326, -31.2585)
  arc A246 (-4.1749, -31.1226) -> (-4.4326, -31.2585) centre (-4.2067, -31.3746) ccw
  line L148 (-4.1749, -31.1226) -> (-3.6962, -31.1831)
  arc A247 (-3.4803, -31.3788) -> (-3.6962, -31.1831) centre (-3.728, -31.4351) ccw
  line L149 (-3.4803, -31.3788) -> (-3.3798, -31.8211)
  arc A248 (-3.3798, -31.8211) -> (-3.2689, -31.9193) centre (-3.256, -31.793) ccw
  arc A249 (-3.2689, -31.9193) -> (-2.7701, -31.9665) centre (0, 0) ccw
  arc A250 (-2.7701, -31.9665) -> (-2.6427, -31.8908) centre (-2.7591, -31.84) ccw
  line L150 (-2.6427, -31.8908) -> (-2.4611, -31.4752)
  arc A251 (-2.2124, -31.3234) -> (-2.4611, -31.4752) centre (-2.2284, -31.5769) ccw
  line L151 (-2.2124, -31.3234) -> (-1.7309, -31.3537)
  arc A252 (-1.5032, -31.5355) -> (-1.7309, -31.3537) centre (-1.7468, -31.6072) ccw
  line L152 (-1.5032, -31.5355) -> (-1.3751, -31.9706)
  arc A253 (-1.3751, -31.9706) -> (-1.2583, -32.0616) centre (-1.2533, -31.9347) ccw
  arc A254 (-1.2583, -32.0616) -> (-0.7574, -32.0773) centre (0, 0) ccw
  arc A255 (-0.7574, -32.0773) -> (-0.6351, -31.9938) centre (-0.7544, -31.9504) ccw
  line L153 (-0.6351, -31.9938) -> (-0.4799, -31.5676)
  arc A256 (-0.2412, -31.4005) -> (-0.4799, -31.5676) centre (-0.2412, -31.6545) ccw
  line L154 (-0.2412, -31.4005) -> (0.2412, -31.4005)
  arc A257 (0.4799, -31.5676) -> (0.2412, -31.4005) centre (0.2412, -31.6545) ccw
  line L155 (0.4799, -31.5676) -> (0.6351, -31.9938)
  arc A258 (0.6351, -31.9938) -> (0.7574, -32.0773) centre (0.7544, -31.9504) ccw
  arc A259 (0.7574, -32.0773) -> (1.2583, -32.0616) centre (0, 0) ccw
  arc A260 (1.2583, -32.0616) -> (1.3751, -31.9706) centre (1.2533, -31.9347) ccw
  line L156 (1.3751, -31.9706) -> (1.5032, -31.5355)
  arc A261 (1.7309, -31.3537) -> (1.5032, -31.5355) centre (1.7468, -31.6072) ccw
  line L157 (1.7309, -31.3537) -> (2.2124, -31.3234)
  arc A262 (2.4611, -31.4752) -> (2.2124, -31.3234) centre (2.2284, -31.5769) ccw
  line L158 (2.4611, -31.4752) -> (2.6427, -31.8908)
  arc A263 (2.6427, -31.8908) -> (2.7701, -31.9665) centre (2.7591, -31.84) ccw
  arc A264 (2.7701, -31.9665) -> (3.2689, -31.9193) centre (0, 0) ccw
  arc A265 (3.2689, -31.9193) -> (3.3798, -31.8211) centre (3.256, -31.793) ccw
  line L159 (3.3798, -31.8211) -> (3.4803, -31.3788)
  arc A266 (3.6962, -31.1831) -> (3.4803, -31.3788) centre (3.728, -31.4351) ccw
  line L160 (3.6962, -31.1831) -> (4.1749, -31.1226)
  arc A267 (4.4326, -31.2585) -> (4.1749, -31.1226) centre (4.2067, -31.3746) ccw
  line L161 (4.4326, -31.2585) -> (4.6399, -31.6619)
  arc A268 (4.6399, -31.6619) -> (4.7718, -31.7295) centre (4.7529, -31.6039) ccw
  arc A269 (4.7718, -31.7295) -> (5.2667, -31.6511) centre (0, 0) ccw
  arc A270 (5.2667, -31.6511) -> (5.3712, -31.5461) centre (5.2459, -31.5258) ccw
  line L162 (5.3712, -31.5461) -> (5.4438, -31.0984)
  arc A271 (5.6469, -30.8895) -> (5.4438, -31.0984) centre (5.6945, -31.139) ccw
  line L163 (5.6469, -30.8895) -> (6.1208, -30.7991)
  arc A272 (6.3866, -30.9185) -> (6.1208, -30.7991) centre (6.1684, -31.0486) ccw
  line L164 (6.3866, -30.9185) -> (6.6188, -31.3081)
  arc A273 (6.6188, -31.3081) -> (6.7547, -31.3672) centre (6.7279, -31.2431) ccw
  arc A274 (6.7547, -31.3672) -> (7.2437, -31.2579) centre (0, 0) ccw
  arc A275 (7.2437, -31.2579) -> (7.3414, -31.1466) centre (7.215, -31.1342) ccw
  line L165 (7.3414, -31.1466) -> (7.3857, -30.6952)
  arc A276 (7.5753, -30.474) -> (7.3857, -30.6952) centre (7.6385, -30.72) ccw
  line L166 (7.5753, -30.474) -> (8.0427, -30.354)
  arc A277 (8.3154, -30.4565) -> (8.0427, -30.354) centre (8.1058, -30.6) ccw
  line L167 (8.3154, -30.4565) -> (8.5716, -30.8307)
  arc A278 (8.5716, -30.8307) -> (8.7109, -30.8812) centre (8.6764, -30.759) ccw
  arc A279 (8.7109, -30.8812) -> (9.1921, -30.7414) centre (0, 0) ccw
  arc A280 (9.1921, -30.7414) -> (9.2827, -30.6242) centre (9.1557, -30.6197) ccw
  line L168 (9.2827, -30.6242) -> (9.2985, -30.1709)
  arc A281 (9.4738, -29.9382) -> (9.2985, -30.1709) centre (9.5523, -30.1798) ccw
  line L169 (9.4738, -29.9382) -> (9.9327, -29.7891)
  arc A282 (10.2114, -29.8743) -> (9.9327, -29.7891) centre (10.0112, -30.0307) ccw
  line L170 (10.2114, -29.8743) -> (10.4906, -30.2317)
  arc A283 (10.4906, -30.2317) -> (10.6328, -30.2733) centre (10.5907, -30.1535) ccw
  arc A284 (10.6328, -30.2733) -> (11.1043, -30.1036) centre (0, 0) ccw
  arc A285 (11.1043, -30.1036) -> (11.1872, -29.9809) centre (11.0603, -29.9844) ccw
  line L171 (11.1872, -29.9809) -> (11.1746, -29.5275)
  arc A286 (11.335, -29.2842) -> (11.1746, -29.5275) centre (11.4285, -29.5204) ccw
  line L172 (11.335, -29.2842) -> (11.7836, -29.1066)
  arc A287 (12.067, -29.1741) -> (11.7836, -29.1066) centre (11.8771, -29.3428) ccw
  line L173 (12.067, -29.1741) -> (12.3682, -29.5133)
  arc A288 (12.3682, -29.5133) -> (12.5127, -29.5459) centre (12.4631, -29.429) ccw
  arc A289 (12.5127, -29.5459) -> (12.9726, -29.3469) centre (0, 0) ccw
  arc A290 (12.9726, -29.3469) -> (13.0477, -29.2193) centre (12.9212, -29.2308) ccw
  line L174 (13.0477, -29.2193) -> (13.0066, -28.7676)
  arc A291 (13.1514, -28.5147) -> (13.0066, -28.7676) centre (13.2595, -28.7446) ccw
  line L175 (13.1514, -28.5147) -> (13.588, -28.3093)
  arc A292 (13.8751, -28.3589) -> (13.588, -28.3093) centre (13.6961, -28.5391) ccw
  line L176 (13.8751, -28.3589) -> (14.1969, -28.6785)
  arc A293 (14.1969, -28.6785) -> (14.3432, -28.702) centre (14.2864, -28.5884) ccw
  arc A294 (14.3432, -28.702) -> (14.7897, -28.4745) centre (0, 0) ccw
  arc A295 (14.7897, -28.4745) -> (14.8566, -28.3423) centre (14.7311, -28.3618) ccw
  line L177 (14.8566, -28.3423) -> (14.7872, -27.8941)
  arc A296 (14.9159, -27.6327) -> (14.7872, -27.8941) centre (15.0383, -27.8553) ccw
  line L178 (14.9159, -27.6327) -> (15.3387, -27.4002)
  arc A297 (15.6284, -27.4317) -> (15.3387, -27.4002) centre (15.4611, -27.6228) ccw
  line L179 (15.6284, -27.4317) -> (15.9696, -27.7305)
  arc A298 (15.9696, -27.7305) -> (16.1171, -27.7447) centre (16.0533, -27.6349) ccw
  arc A299 (16.1171, -27.7447) -> (16.5484, -27.4896) centre (0, 0) ccw
  arc A300 (16.5484, -27.4896) -> (16.6069, -27.3536) centre (16.4829, -27.3808) ccw
  line L180 (16.6069, -27.3536) -> (16.5096, -26.9106)
  arc A301 (16.6215, -26.6416) -> (16.5096, -26.9106) centre (16.7576, -26.856) ccw
  line L181 (16.6215, -26.6416) -> (17.0289, -26.383)
  arc A302 (17.32, -26.3963) -> (17.0289, -26.383) centre (17.165, -26.5975) ccw
  line L182 (17.32, -26.3963) -> (17.6793, -26.673)
  arc A303 (17.6793, -26.673) -> (17.8274, -26.678) centre (17.7568, -26.5724) ccw
  arc A304 (17.8274, -26.678) -> (18.2418, -26.3963) centre (0, 0) ccw
  arc A305 (18.2418, -26.3963) -> (18.2917, -26.2568) centre (18.1696, -26.2918) ccw
  line L183 (18.2917, -26.2568) -> (18.1667, -25.8208)
  arc A306 (18.2616, -25.5453) -> (18.1667, -25.8208) centre (18.4109, -25.7508) ccw
  line L184 (18.2616, -25.5453) -> (18.6519, -25.2617)
  arc A307 (18.9432, -25.2566) -> (18.6519, -25.2617) centre (18.8012, -25.4672) ccw
  line L185 (18.9432, -25.2566) -> (19.3193, -25.5103)
  arc A308 (19.3193, -25.5103) -> (19.4673, -25.5059) centre (19.3903, -25.405) ccw
  arc A309 (19.4673, -25.5059) -> (19.8633, -25.1988) centre (0, 0) ccw
  arc A310 (19.8633, -25.1988) -> (19.9043, -25.0565) centre (19.7847, -25.0991) ccw
  line L186 (19.9043, -25.0565) -> (19.7522, -24.6292)
  arc A311 (19.8295, -24.3483) -> (19.7522, -24.6292) centre (19.9914, -24.544) ccw
  line L187 (19.8295, -24.3483) -> (20.2013, -24.0407)
  arc A312 (20.4917, -24.0173) -> (20.2013, -24.0407) centre (20.3632, -24.2364) ccw
  line L188 (20.4917, -24.0173) -> (20.8829, -24.2469)
  arc A313 (20.8829, -24.2469) -> (21.0305, -24.2332) centre (20.9472, -24.1373) ccw
  arc A314 (21.0305, -24.2332) -> (21.4063, -23.9018) centre (0, 0) ccw
  arc A315 (21.4063, -23.9018) -> (21.4383, -23.7572) centre (21.3216, -23.8072) ccw
  line L189 (21.4383, -23.7572) -> (21.2597, -23.3403)
  arc A316 (21.3192, -23.0551) -> (21.2597, -23.3403) centre (21.4931, -23.2403) ccw
  line L190 (21.3192, -23.0551) -> (21.671, -22.7248)
  arc A317 (21.9594, -22.6833) -> (21.671, -22.7248) centre (21.8448, -22.91) ccw
  line L191 (21.9594, -22.6833) -> (22.3642, -22.8878)
  arc A318 (22.3642, -22.8878) -> (22.5106, -22.8649) centre (22.4215, -22.7744) ccw
  arc A319 (22.5106, -22.8649) -> (22.8649, -22.5106) centre (0, 0) ccw
  arc A320 (22.8649, -22.5106) -> (22.8878, -22.3642) centre (22.7744, -22.4215) ccw
  line L192 (22.8878, -22.3642) -> (22.6833, -21.9594)
  arc A321 (22.7248, -21.671) -> (22.6833, -21.9594) centre (22.91, -21.8448) ccw
  line L193 (22.7248, -21.671) -> (23.0551, -21.3192)
  arc A322 (23.3403, -21.2597) -> (23.0551, -21.3192) centre (23.2403, -21.4931) ccw
  line L194 (23.3403, -21.2597) -> (23.7572, -21.4383)
  arc A323 (23.7572, -21.4383) -> (23.9018, -21.4063) centre (23.8072, -21.3216) ccw
  arc A324 (23.9018, -21.4063) -> (24.2332, -21.0305) centre (0, 0) ccw
  arc A325 (24.2332, -21.0305) -> (24.2469, -20.8829) centre (24.1373, -20.9472) ccw
  line L195 (24.2469, -20.8829) -> (24.0173, -20.4917)
  arc A326 (24.0407, -20.2013) -> (24.0173, -20.4917) centre (24.2364, -20.3632) ccw
  line L196 (24.0407, -20.2013) -> (24.3483, -19.8295)
  arc A327 (24.6292, -19.7522) -> (24.3483, -19.8295) centre (24.544, -19.9914) ccw
  line L197 (24.6292, -19.7522) -> (25.0565, -19.9043)
  arc A328 (25.0565, -19.9043) -> (25.1988, -19.8633) centre (25.0991, -19.7847) ccw
  arc A329 (25.1988, -19.8633) -> (25.5059, -19.4673) centre (0, 0) ccw
  arc A330 (25.5059, -19.4673) -> (25.5103, -19.3193) centre (25.405, -19.3903) ccw
  line L198 (25.5103, -19.3193) -> (25.2566, -18.9432)
  arc A331 (25.2617, -18.6519) -> (25.2566, -18.9432) centre (25.4672, -18.8012) ccw
  line L199 (25.2617, -18.6519) -> (25.5453, -18.2616)
  arc A332 (25.8208, -18.1667) -> (25.5453, -18.2616) centre (25.7508, -18.4109) ccw
  line L200 (25.8208, -18.1667) -> (26.2568, -18.2917)
  arc A333 (26.2568, -18.2917) -> (26.3963, -18.2418) centre (26.2918, -18.1696) ccw
  arc A334 (26.3963, -18.2418) -> (26.678, -17.8274) centre (0, 0) ccw
  arc A335 (26.678, -17.8274) -> (26.673, -17.6793) centre (26.5724, -17.7568) ccw
  line L201 (26.673, -17.6793) -> (26.3963, -17.32)
  arc A336 (26.383, -17.0289) -> (26.3963, -17.32) centre (26.5975, -17.165) ccw
  line L202 (26.383, -17.0289) -> (26.6416, -16.6215)
  arc A337 (26.9106, -16.5096) -> (26.6416, -16.6215) centre (26.856, -16.7576) ccw
  line L203 (26.9106, -16.5096) -> (27.3536, -16.6069)
  arc A338 (27.3536, -16.6069) -> (27.4896, -16.5484) centre (27.3808, -16.4829) ccw
  arc A339 (27.4896, -16.5484) -> (27.7447, -16.1171) centre (0, 0) ccw
  arc A340 (27.7447, -16.1171) -> (27.7305, -15.9696) centre (27.6349, -16.0533) ccw
  line L204 (27.7305, -15.9696) -> (27.4317, -15.6284)
  arc A341 (27.4002, -15.3387) -> (27.4317, -15.6284) centre (27.6228, -15.4611) ccw
  line L205 (27.4002, -15.3387) -> (27.6327, -14.9159)
  arc A342 (27.8941, -14.7872) -> (27.6327, -14.9159) centre (27.8553, -15.0383) ccw
  line L206 (27.8941, -14.7872) -> (28.3423, -14.8566)
  arc A343 (28.3423, -14.8566) -> (28.4745, -14.7897) centre (28.3618, -14.7311) ccw
  arc A344 (28.4745, -14.7897) -> (28.702, -14.3432) centre (0, 0) ccw
  arc A345 (28.702, -14.3432) -> (28.6785, -14.1969) centre (28.5884, -14.2864) ccw
  line L207 (28.6785, -14.1969) -> (28.3589, -13.8751)
  arc A346 (28.3093, -13.588) -> (28.3589, -13.8751) centre (28.5391, -13.6961) ccw
  line L208 (28.3093, -13.588) -> (28.5147, -13.1514)
  arc A347 (28.7676, -13.0066) -> (28.5147, -13.1514) centre (28.7446, -13.2595) ccw
  line L209 (28.7676, -13.0066) -> (29.2193, -13.0477)
  arc A348 (29.2193, -13.0477) -> (29.3469, -12.9726) centre (29.2308, -12.9212) ccw
  arc A349 (29.3469, -12.9726) -> (29.5459, -12.5127) centre (0, 0) ccw
  arc A350 (29.5459, -12.5127) -> (29.5133, -12.3682) centre (29.429, -12.4631) ccw
  line L210 (29.5133, -12.3682) -> (29.1741, -12.067)
  arc A351 (29.1066, -11.7836) -> (29.1741, -12.067) centre (29.3428, -11.8771) ccw
  line L211 (29.1066, -11.7836) -> (29.2842, -11.335)
  arc A352 (29.5275, -11.1746) -> (29.2842, -11.335) centre (29.5204, -11.4285) ccw
  line L212 (29.5275, -11.1746) -> (29.9809, -11.1872)
  arc A353 (29.9809, -11.1872) -> (30.1036, -11.1043) centre (29.9844, -11.0603) ccw
  arc A354 (30.1036, -11.1043) -> (30.2733, -10.6328) centre (0, 0) ccw
  arc A355 (30.2733, -10.6328) -> (30.2317, -10.4906) centre (30.1535, -10.5907) ccw
  line L213 (30.2317, -10.4906) -> (29.8743, -10.2114)
  arc A356 (29.7891, -9.9327) -> (29.8743, -10.2114) centre (30.0307, -10.0112) ccw
  line L214 (29.7891, -9.9327) -> (29.9382, -9.4738)
  arc A357 (30.1709, -9.2985) -> (29.9382, -9.4738) centre (30.1798, -9.5523) ccw
  line L215 (30.1709, -9.2985) -> (30.6242, -9.2827)
  arc A358 (30.6242, -9.2827) -> (30.7414, -9.1921) centre (30.6197, -9.1557) ccw
  arc A359 (30.7414, -9.1921) -> (30.8812, -8.7109) centre (0, 0) ccw
  arc A360 (30.8812, -8.7109) -> (30.8307, -8.5716) centre (30.759, -8.6764) ccw
  line L216 (30.8307, -8.5716) -> (30.4565, -8.3154)
  arc A361 (30.354, -8.0427) -> (30.4565, -8.3154) centre (30.6, -8.1058) ccw
  line L217 (30.354, -8.0427) -> (30.474, -7.5753)
  arc A362 (30.6952, -7.3857) -> (30.474, -7.5753) centre (30.72, -7.6385) ccw
  line L218 (30.6952, -7.3857) -> (31.1466, -7.3414)
  arc A363 (31.1466, -7.3414) -> (31.2579, -7.2437) centre (31.1342, -7.215) ccw
  arc A364 (31.2579, -7.2437) -> (31.3672, -6.7547) centre (0, 0) ccw
  arc A365 (31.3672, -6.7547) -> (31.3081, -6.6188) centre (31.2431, -6.7279) ccw
  line L219 (31.3081, -6.6188) -> (30.9185, -6.3866)
  arc A366 (30.7991, -6.1208) -> (30.9185, -6.3866) centre (31.0486, -6.1684) ccw
  line L220 (30.7991, -6.1208) -> (30.8895, -5.6469)
  arc A367 (31.0984, -5.4438) -> (30.8895, -5.6469) centre (31.139, -5.6945) ccw
  line L221 (31.0984, -5.4438) -> (31.5461, -5.3712)
  arc A368 (31.5461, -5.3712) -> (31.6511, -5.2667) centre (31.5258, -5.2459) ccw
  arc A369 (31.6511, -5.2667) -> (31.7295, -4.7718) centre (0, 0) ccw
  arc A370 (31.7295, -4.7718) -> (31.6619, -4.6399) centre (31.6039, -4.7529) ccw
  line L222 (31.6619, -4.6399) -> (31.2585, -4.4326)
  arc A371 (31.1226, -4.1749) -> (31.2585, -4.4326) centre (31.3746, -4.2067) ccw
  line L223 (31.1226, -4.1749) -> (31.1831, -3.6962)
  arc A372 (31.3788, -3.4803) -> (31.1831, -3.6962) centre (31.4351, -3.728) ccw
  line L224 (31.3788, -3.4803) -> (31.8211, -3.3798)
  arc A373 (31.8211, -3.3798) -> (31.9193, -3.2689) centre (31.793, -3.256) ccw
  arc A374 (31.9193, -3.2689) -> (31.9665, -2.7701) centre (0, 0) ccw
  arc A375 (31.9665, -2.7701) -> (31.8908, -2.6427) centre (31.84, -2.7591) ccw
  line L225 (31.8908, -2.6427) -> (31.4752, -2.4611)
  arc A376 (31.3234, -2.2124) -> (31.4752, -2.4611) centre (31.5769, -2.2284) ccw
  line L226 (31.3234, -2.2124) -> (31.3537, -1.7309)
  arc A377 (31.5355, -1.5032) -> (31.3537, -1.7309) centre (31.6072, -1.7468) ccw
  line L227 (31.5355, -1.5032) -> (31.9706, -1.3751)
  arc A378 (31.9706, -1.3751) -> (32.0616, -1.2583) centre (31.9347, -1.2533) ccw
  arc A379 (32.0616, -1.2583) -> (32.0773, -0.7574) centre (0, 0) ccw
  arc A380 (32.0773, -0.7574) -> (31.9938, -0.6351) centre (31.9504, -0.7544) ccw
  line L228 (31.9938, -0.6351) -> (31.5676, -0.4799)
  arc A381 (31.4005, -0.2412) -> (31.5676, -0.4799) centre (31.6545, -0.2412) ccw
  line L229 (31.4005, -0.2412) -> (31.4005, 0.2412)
  arc A382 (31.5676, 0.4799) -> (31.4005, 0.2412) centre (31.6545, 0.2412) ccw
  line L230 (31.5676, 0.4799) -> (31.9938, 0.6351)
  arc A383 (31.9938, 0.6351) -> (32.0773, 0.7574) centre (31.9504, 0.7544) ccw
  arc A384 (32.0773, 0.7574) -> (32.0616, 1.2583) centre (0, 0) ccw
  arc A385 (32.0616, 1.2583) -> (31.9706, 1.3751) centre (31.9347, 1.2533) ccw
  line L231 (31.9706, 1.3751) -> (31.5355, 1.5032)
  arc A386 (31.3537, 1.7309) -> (31.5355, 1.5032) centre (31.6072, 1.7468) ccw
  line L232 (31.3537, 1.7309) -> (31.3234, 2.2124)
  arc A387 (31.4752, 2.4611) -> (31.3234, 2.2124) centre (31.5769, 2.2284) ccw
  line L233 (31.4752, 2.4611) -> (31.8908, 2.6427)
  arc A388 (31.8908, 2.6427) -> (31.9665, 2.7701) centre (31.84, 2.7591) ccw
  arc A389 (31.9665, 2.7701) -> (31.9193, 3.2689) centre (0, 0) ccw
  arc A390 (31.9193, 3.2689) -> (31.8211, 3.3798) centre (31.793, 3.256) ccw
  line L234 (31.8211, 3.3798) -> (31.3788, 3.4803)
  arc A391 (31.1831, 3.6962) -> (31.3788, 3.4803) centre (31.4351, 3.728) ccw
  line L235 (31.1831, 3.6962) -> (31.1226, 4.1749)
  arc A392 (31.2585, 4.4326) -> (31.1226, 4.1749) centre (31.3746, 4.2067) ccw
  line L236 (31.2585, 4.4326) -> (31.6619, 4.6399)
  arc A393 (31.6619, 4.6399) -> (31.7295, 4.7718) centre (31.6039, 4.7529) ccw
  arc A394 (31.7295, 4.7718) -> (31.6511, 5.2667) centre (0, 0) ccw
  arc A395 (31.6511, 5.2667) -> (31.5461, 5.3712) centre (31.5258, 5.2459) ccw
  line L237 (31.5461, 5.3712) -> (31.0984, 5.4438)
  arc A396 (30.8895, 5.6469) -> (31.0984, 5.4438) centre (31.139, 5.6945) ccw
  line L238 (30.8895, 5.6469) -> (30.7991, 6.1208)
  arc A397 (30.9185, 6.3866) -> (30.7991, 6.1208) centre (31.0486, 6.1684) ccw
  line L239 (30.9185, 6.3866) -> (31.3081, 6.6188)
  arc A398 (31.3081, 6.6188) -> (31.3672, 6.7547) centre (31.2431, 6.7279) ccw
  arc A399 (31.3672, 6.7547) -> (31.2579, 7.2437) centre (0, 0) ccw
  arc A400 (31.2579, 7.2437) -> (31.1466, 7.3414) centre (31.1342, 7.215) ccw
  line L240 (31.1466, 7.3414) -> (30.6952, 7.3857)
  arc A401 (30.474, 7.5753) -> (30.6952, 7.3857) centre (30.72, 7.6385) ccw
  line L241 (30.474, 7.5753) -> (30.354, 8.0427)
  arc A402 (30.4565, 8.3154) -> (30.354, 8.0427) centre (30.6, 8.1058) ccw
  line L242 (30.4565, 8.3154) -> (30.8307, 8.5716)
  arc A403 (30.8307, 8.5716) -> (30.8812, 8.7109) centre (30.759, 8.6764) ccw
  arc A404 (30.8812, 8.7109) -> (30.7414, 9.1921) centre (0, 0) ccw
  arc A405 (30.7414, 9.1921) -> (30.6242, 9.2827) centre (30.6197, 9.1557) ccw
  line L243 (30.6242, 9.2827) -> (30.1709, 9.2985)
  arc A406 (29.9382, 9.4738) -> (30.1709, 9.2985) centre (30.1798, 9.5523) ccw
  line L244 (29.9382, 9.4738) -> (29.7891, 9.9327)
  arc A407 (29.8743, 10.2114) -> (29.7891, 9.9327) centre (30.0307, 10.0112) ccw
  line L245 (29.8743, 10.2114) -> (30.2317, 10.4906)
  arc A408 (30.2317, 10.4906) -> (30.2733, 10.6328) centre (30.1535, 10.5907) ccw
  arc A409 (30.2733, 10.6328) -> (30.1036, 11.1043) centre (0, 0) ccw
  arc A410 (30.1036, 11.1043) -> (29.9809, 11.1872) centre (29.9844, 11.0603) ccw
  line L246 (29.9809, 11.1872) -> (29.5275, 11.1746)
  arc A411 (29.2842, 11.335) -> (29.5275, 11.1746) centre (29.5204, 11.4285) ccw
  line L247 (29.2842, 11.335) -> (29.1066, 11.7836)
  arc A412 (29.1741, 12.067) -> (29.1066, 11.7836) centre (29.3428, 11.8771) ccw
  line L248 (29.1741, 12.067) -> (29.5133, 12.3682)
  arc A413 (29.5133, 12.3682) -> (29.5459, 12.5127) centre (29.429, 12.4631) ccw
  arc A414 (29.5459, 12.5127) -> (29.3469, 12.9726) centre (0, 0) ccw
  arc A415 (29.3469, 12.9726) -> (29.2193, 13.0477) centre (29.2308, 12.9212) ccw
  line L249 (29.2193, 13.0477) -> (28.7676, 13.0066)
  arc A416 (28.5147, 13.1514) -> (28.7676, 13.0066) centre (28.7446, 13.2595) ccw
  line L250 (28.5147, 13.1514) -> (28.3093, 13.588)
  arc A417 (28.3589, 13.8751) -> (28.3093, 13.588) centre (28.5391, 13.6961) ccw
  line L251 (28.3589, 13.8751) -> (28.6785, 14.1969)
  arc A418 (28.6785, 14.1969) -> (28.702, 14.3432) centre (28.5884, 14.2864) ccw
  arc A419 (28.702, 14.3432) -> (28.4745, 14.7897) centre (0, 0) ccw
  arc A420 (28.4745, 14.7897) -> (28.3423, 14.8566) centre (28.3618, 14.7311) ccw
  line L252 (28.3423, 14.8566) -> (27.8941, 14.7872)
  arc A421 (27.6327, 14.9159) -> (27.8941, 14.7872) centre (27.8553, 15.0383) ccw
  line L253 (27.6327, 14.9159) -> (27.4002, 15.3387)
  arc A422 (27.4317, 15.6284) -> (27.4002, 15.3387) centre (27.6228, 15.4611) ccw
  line L254 (27.4317, 15.6284) -> (27.7305, 15.9696)
  arc A423 (27.7305, 15.9696) -> (27.7447, 16.1171) centre (27.6349, 16.0533) ccw
  arc A424 (27.7447, 16.1171) -> (27.4896, 16.5484) centre (0, 0) ccw
  arc A425 (27.4896, 16.5484) -> (27.3536, 16.6069) centre (27.3808, 16.4829) ccw
  line L255 (27.3536, 16.6069) -> (26.9106, 16.5096)
  arc A426 (26.6416, 16.6215) -> (26.9106, 16.5096) centre (26.856, 16.7576) ccw
  line L256 (26.6416, 16.6215) -> (26.383, 17.0289)
  arc A427 (26.3963, 17.32) -> (26.383, 17.0289) centre (26.5975, 17.165) ccw
  line L257 (26.3963, 17.32) -> (26.673, 17.6793)
  arc A428 (26.673, 17.6793) -> (26.678, 17.8274) centre (26.5724, 17.7568) ccw
  arc A429 (26.678, 17.8274) -> (26.3963, 18.2418) centre (0, 0) ccw
  arc A430 (26.3963, 18.2418) -> (26.2568, 18.2917) centre (26.2918, 18.1696) ccw
  line L258 (26.2568, 18.2917) -> (25.8208, 18.1667)
  arc A431 (25.5453, 18.2616) -> (25.8208, 18.1667) centre (25.7508, 18.4109) ccw
  line L259 (25.5453, 18.2616) -> (25.2617, 18.6519)
  arc A432 (25.2566, 18.9432) -> (25.2617, 18.6519) centre (25.4672, 18.8012) ccw
  line L260 (25.2566, 18.9432) -> (25.5103, 19.3193)